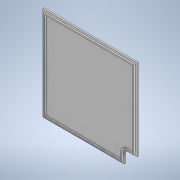
# Autodesk Inventor part: capac_cutie_fum_ok
Saved by Autodesk Inventor 2020 (Build 240168000, 168)
## iProperties
Created: 2023-05-09
Part Number: capac_cutie_fum_ok
Material: Generic
Document SubType Name: Modeling
Designer: user
Density: 1 g/cm^3
Appearance: Default
Author: user
Autodesk Inventor part; units mm, degrees
ref_plane "YZ Plane" through (0, 0, 0) normal (1, 0, 0) x (0, 1, 0)
ref_plane "XZ Plane" through (0, 0, 0) normal (0, 1, 0) x (-1, 0, 0)
ref_plane "XY Plane" through (0, 0, 0) normal (0, 0, 1) x (1, 0, 0)
sketch "Sketch1" plane through (0, 0, 0) normal (0, 0, 1) x (1, 0, 0)
  line L0 (-146.0992, 200.0158) -> (3.6008, 200.0158)
  line L1 (3.6008, 200.0158) -> (3.6008, 50.3158)
  line L2 (3.6008, 50.3158) -> (-146.0992, 50.3158)
  line L3 (-146.0992, 50.3158) -> (-146.0992, 200.0158)
  line L4 (-144.0992, 198.0158) -> (1.6008, 198.0158)
  line L5 (1.6008, 198.0158) -> (1.6008, 52.3158)
  line L6 (1.6008, 52.3158) -> (-144.0992, 52.3158)
  line L7 (-144.0992, 52.3158) -> (-144.0992, 198.0158)
  line L8 (3.6008, 50.3158) -> (-16.3992, 50.3158)
  line L9 (-16.3992, 50.3158) -> (-16.3992, 64.0158)
  line L10 (-10.0992, 70.3158) -> (3.6008, 70.3158)
  line L11 (3.6008, 70.3158) -> (3.6008, 50.3158)
  arc A0 (-10.0992, 70.3158) -> (-16.3992, 64.0158) centre (-10.0992, 64.0158) ccw
  line L12 (3.6008, 50.3158) -> (-18.3992, 50.3158)
  line L13 (-18.3992, 50.3158) -> (-18.3992, 66.0158)
  line L14 (-12.0992, 72.3158) -> (3.6008, 72.3158)
  line L15 (3.6008, 72.3158) -> (3.6008, 50.3158)
  arc A1 (-12.0992, 72.3158) -> (-18.3992, 66.0158) centre (-12.0992, 66.0158) ccw
  point P0 (0, 0)
  point P1 (-16.3992, 70.3158)
  point P2 (-18.3992, 72.3158)
  point P3 (-16.3992, 52.3158)
  point P4 (1.6008, 70.3158)
  point P5 (-18.3992, 50.3158)
  point P6 (3.6008, 72.3158)
  dimension "d0" = 149.7
  dimension "d1" = 149.7
  dimension "d2" = 2
  dimension "d3" = 2
  dimension "d4" = 2
  dimension "d5" = 2
  dimension "d6" = 20
  dimension "d7" = 20
  dimension "d8" = 6.3
  dimension "d9" = 22
  dimension "d10" = 22
  dimension "d11" = 6.3
  constraints: 32 end point, 8 parallel, 4 horizontal, 4 perpendicular, 4 point on circle, 4 point on line, 4 tangent, 2 centre point
  measures "d0" distance between parallel lines of L1 L3
  measures "d1" distance between parallel lines of L2 L0
  measures "d2" distance between parallel lines of L3 L7
  measures "d3" distance between parallel lines of L2 L6
  measures "d4" distance between parallel lines of L1 L5
  measures "d5" distance between parallel lines of L0 L4
  measures "d6" distance of point (-16.399, 70.316) L10.end
  measures "d7" distance between parallel lines of L2 L10
  measures "d8" radius of A0
  measures "d9" distance of point (-18.399, 72.316) L14.end
  measures "d10" distance between parallel lines of L2 L14
  measures "d11" radius of A1
extrude "Extrusion1" add sketch "Sketch1" along normal blind 2.2 contours L0 L1 L14 L5 L4 L7 L6 L13 L2 L3 | L1 L10 L5 L14 | L13 L6 L9 L2 | L5 L10 A0 L9 L6 L13 A1 L14
sketch "Sketch2" plane through (0, 0, 0) normal (0, 0, -1) x (-1, 0, 0)
  line L0 (146.0992, 50.3158) -> (16.3992, 50.3158) projected
  line L1 (146.0992, 200.0158) -> (146.0992, 50.3158) projected
  line L2 (-3.6008, 200.0158) -> (146.0992, 200.0158) projected
  line L3 (-3.6008, 70.3158) -> (-3.6008, 200.0158) projected
  line L4 (10.0992, 70.3158) -> (-3.6008, 70.3158) projected
  arc A0 (16.3992, 64.0158) -> (10.0992, 70.3158) centre (10.0992, 64.0158) ccw projected
  line L5 (16.3992, 50.3158) -> (16.3992, 64.0158) projected
  line L6 (18.3992, 52.3158) -> (144.0992, 52.3158) projected
  line L7 (18.3992, 66.0158) -> (18.3992, 52.3158) projected
  arc A1 (18.3992, 66.0158) -> (12.0992, 72.3158) centre (12.0992, 66.0158) ccw projected
  line L8 (-1.6008, 72.3158) -> (12.0992, 72.3158) projected
  line L9 (-1.6008, 198.0158) -> (-1.6008, 72.3158) projected
  line L10 (144.0992, 198.0158) -> (-1.6008, 198.0158) projected
  line L11 (144.0992, 52.3158) -> (144.0992, 198.0158) projected
  line L12 (149.3992, 47.3158) -> (14.6492, 47.3158)
  line L13 (-6.6008, 68.5658) -> (-6.6008, 203.3158)
  line L14 (-6.6008, 203.3158) -> (149.3992, 203.3158)
  line L15 (149.3992, 203.3158) -> (149.3992, 47.3158)
  line L16 (14.6492, 47.3158) -> (14.6492, 62.2658)
  line L17 (8.3492, 68.5658) -> (-6.6008, 68.5658)
  arc A2 (14.6492, 62.2658) -> (8.3492, 68.5658) centre (8.3492, 62.2658) ccw
  point P0 (0, 0)
  dimension "d14" = 156
  dimension "d15" = 156
  dimension "d16" = 3
  dimension "d17" = 3
  dimension "d18" = 1.75
  dimension "d19" = 1.75
  dimension "d20" = 6.3
  constraints: 12 end point, 2 parallel, 2 point on circle, 2 tangent, 1 centre point, 1 horizontal, 1 perpendicular
  measures "d14" distance between parallel lines of L13 L15
  measures "d15" distance between parallel lines of L14 L12
  measures "d16" distance between parallel lines of L3 L13
  measures "d17" distance between parallel lines of L0 L12
  measures "d18" distance between parallel lines of L5 L16
  measures "d19" distance between parallel lines of L4 L17
  measures "d20" radius of A2
extrude "Extrusion2" add sketch "Sketch2" along normal blind 2.2 contours L0 L5 A0 L4 L3 L2 L1 | L7 A1 L8 L9 L10 L11 L6 | L12 L16 A2 L17 L13 L14 L15
body "Solid1"
